veebikaamera-post-v2-standalone (Autodesk Fusion 360 design; units mm, degrees)
part number: 2026-10-23-17-59-02-011
part number: 2026-10-23-17-59-03-726
part number: 2026-10-23-17-59-05-380
part number: 2026-10-23-18-11-50-631
part number: 2026-10-23-18-11-50-740
Autodesk Fusion 360 part; units mm, degrees
ref_plane "WorkPlane1" through (0, 0, 7.28) normal (0, 0, 1) x (1, 0, 0) in component "webcam_post_lower"
sketch "Sketch1" plane through (0, 0, 7.28) normal (0, 0, 1) x (1, 0, 0) in component "webcam_post_lower"
  line L0 (-332.65, -126.4) -> (-408.35, -126.4)
  line L1 (-412.1, -130.15) -> (-412.1, -205.85)
  line L2 (-408.35, -209.6) -> (-332.65, -209.6)
  line L3 (-328.9, -205.85) -> (-328.9, -130.15)
  arc A0 (-408.35, -126.4) -> (-412.1, -130.15) centre (-408.35, -130.15) ccw
  arc A1 (-412.1, -205.85) -> (-408.35, -209.6) centre (-408.35, -205.85) ccw
  arc A2 (-332.65, -209.6) -> (-328.9, -205.85) centre (-332.65, -205.85) ccw
  arc A3 (-328.9, -130.15) -> (-332.65, -126.4) centre (-332.65, -130.15) ccw
  constraint tangent L0 A0
  constraint tangent L1 A0
  constraint tangent L1 A1
  constraint tangent L2 A1
  constraint tangent L2 A2
  constraint tangent L3 A2
  constraint tangent L3 A3
  constraint tangent L0 A3
extrude "Extrude1" add sketch "Sketch1" along normal blind 6 makes body 1 in component "webcam_post_lower"
ref_plane "WorkPlane2" through (0, 0, 7.28) normal (0, 0, 1) x (1, 0, 0) in component "webcam_post_lower"
sketch "Sketch2" plane through (0, 0, 7.28) normal (0, 0, 1) x (1, 0, 0) in component "webcam_post_lower"
  line L0 (-375.11, -171.11) -> (-407.89, -171.11)
  line L1 (-409.39, -172.61) -> (-409.39, -205.39)
  line L2 (-407.89, -206.89) -> (-375.11, -206.89)
  line L3 (-373.61, -205.39) -> (-373.61, -172.61)
  arc A0 (-407.89, -171.11) -> (-409.39, -172.61) centre (-407.89, -172.61) ccw
  arc A1 (-409.39, -205.39) -> (-407.89, -206.89) centre (-407.89, -205.39) ccw
  arc A2 (-375.11, -206.89) -> (-373.61, -205.39) centre (-375.11, -205.39) ccw
  arc A3 (-373.61, -172.61) -> (-375.11, -171.11) centre (-375.11, -172.61) ccw
  line L4 (-375.11, -129.11) -> (-407.89, -129.11)
  line L5 (-409.39, -130.61) -> (-409.39, -163.39)
  line L6 (-407.89, -164.89) -> (-375.11, -164.89)
  line L7 (-373.61, -163.39) -> (-373.61, -130.61)
  arc A4 (-407.89, -129.11) -> (-409.39, -130.61) centre (-407.89, -130.61) ccw
  arc A5 (-409.39, -163.39) -> (-407.89, -164.89) centre (-407.89, -163.39) ccw
  arc A6 (-375.11, -164.89) -> (-373.61, -163.39) centre (-375.11, -163.39) ccw
  arc A7 (-373.61, -130.61) -> (-375.11, -129.11) centre (-375.11, -130.61) ccw
  line L8 (-333.11, -171.11) -> (-365.89, -171.11)
  line L9 (-367.39, -172.61) -> (-367.39, -205.39)
  line L10 (-365.89, -206.89) -> (-333.11, -206.89)
  line L11 (-331.61, -205.39) -> (-331.61, -172.61)
  arc A8 (-365.89, -171.11) -> (-367.39, -172.61) centre (-365.89, -172.61) ccw
  arc A9 (-367.39, -205.39) -> (-365.89, -206.89) centre (-365.89, -205.39) ccw
  arc A10 (-333.11, -206.89) -> (-331.61, -205.39) centre (-333.11, -205.39) ccw
  arc A11 (-331.61, -172.61) -> (-333.11, -171.11) centre (-333.11, -172.61) ccw
  line L12 (-333.11, -129.11) -> (-365.89, -129.11)
  line L13 (-367.39, -130.61) -> (-367.39, -163.39)
  line L14 (-365.89, -164.89) -> (-333.11, -164.89)
  line L15 (-331.61, -163.39) -> (-331.61, -130.61)
  arc A12 (-365.89, -129.11) -> (-367.39, -130.61) centre (-365.89, -130.61) ccw
  arc A13 (-367.39, -163.39) -> (-365.89, -164.89) centre (-365.89, -163.39) ccw
  arc A14 (-333.11, -164.89) -> (-331.61, -163.39) centre (-333.11, -163.39) ccw
  arc A15 (-331.61, -130.61) -> (-333.11, -129.11) centre (-333.11, -130.61) ccw
  constraint tangent L0 A0
  constraint tangent L1 A0
  constraint tangent L1 A1
  constraint tangent L2 A1
  constraint tangent L2 A2
  constraint tangent L3 A2
  constraint tangent L3 A3
  constraint tangent L0 A3
  constraint tangent L4 A4
  constraint tangent L5 A4
  constraint tangent L5 A5
  constraint tangent L6 A5
  constraint tangent L6 A6
  constraint tangent L7 A6
  constraint tangent L7 A7
  constraint tangent L4 A7
  constraint tangent L8 A8
  constraint tangent L9 A8
  constraint tangent L9 A9
  constraint tangent L10 A9
  constraint tangent L10 A10
  constraint tangent L11 A10
  constraint tangent L11 A11
  constraint tangent L8 A11
  constraint tangent L12 A12
  constraint tangent L13 A12
  constraint tangent L13 A13
  constraint tangent L14 A13
  constraint tangent L14 A14
  constraint tangent L15 A14
  constraint tangent L15 A15
  constraint tangent L12 A15
extrude "Extrude2" add sketch "Sketch2" against normal blind 4.65 bodies 1 in component "webcam_post_lower"
chamfer "Chamfer1" distance 0.5 angle 45 32 edges at (-349.5, -129.11, 2.63) (-332.0493, -129.5493, 2.63) (-331.61, -147, 2.63) (-332.0493, -164.4507, 2.63) (-349.5, -164.89, 2.63) (-366.9507, -164.4507, 2.63) (-367.39, -147, 2.63) (-366.9507, -129.5493, 2.63) (-391.5, -171.11, 2.63) (-374.0493, -171.5493, 2.63) (-373.61, -189, 2.63) (-374.0493, -206.4507, 2.63) (-391.5, -206.89, 2.63) (-408.9507, -206.4507, 2.63) (-409.39, -189, 2.63) (-408.9507, -171.5493, 2.63) (-391.5, -129.11, 2.63) (-374.0493, -129.5493, 2.63) (-373.61, -147, 2.63) (-374.0493, -164.4507, 2.63) (-391.5, -164.89, 2.63) (-408.9507, -164.4507, 2.63) (-409.39, -147, 2.63) (-408.9507, -129.5493, 2.63) (-349.5, -171.11, 2.63) (-332.0493, -171.5493, 2.63) (-331.61, -189, 2.63) (-332.0493, -206.4507, 2.63) (-349.5, -206.89, 2.63) (-366.9507, -206.4507, 2.63) (-367.39, -189, 2.63) (-366.9507, -171.5493, 2.63) tangent chain off on bodies 1 in component "webcam_post_lower"
ref_plane "WorkPlane3" through (0, 0, 7.28) normal (0, 0, 1) x (1, 0, 0) in component "webcam_post_lower"
sketch "Sketch3" plane through (0, 0, 7.28) normal (0, 0, 1) x (1, 0, 0) in component "webcam_post_lower"
  line L0 (-382.1, -179.6) -> (-412.1, -179.6)
  line L1 (-412.1, -179.6) -> (-509.5955, -236.7941)
  line L2 (-509.5955, -236.7941) -> (-509.5955, -266.7941)
  line L3 (-509.5955, -266.7941) -> (-479.5955, -266.7941)
  line L4 (-479.5955, -266.7941) -> (-382.1, -209.6)
  line L5 (-382.1, -209.6) -> (-382.1, -179.6)
extrude "Extrude3" add sketch "Sketch3" along normal blind 30 bodies 1 in component "webcam_post_lower"
ref_plane "WorkPlane4" through (0, 0, 7.28) normal (0, 0, 1) x (1, 0, 0) in component "webcam_post_lower"
sketch "Sketch4" plane through (0, 0, 7.28) normal (0, 0, 1) x (1, 0, 0) in component "webcam_post_lower"
  line L0 (-385.1, -182.6) -> (-409.1, -182.6)
  line L1 (-409.1, -182.6) -> (-506.5955, -239.7941)
  line L2 (-506.5955, -239.7941) -> (-506.5955, -263.7941)
  line L3 (-506.5955, -263.7941) -> (-482.5955, -263.7941)
  line L4 (-482.5955, -263.7941) -> (-385.1, -206.6)
  line L5 (-385.1, -206.6) -> (-385.1, -182.6)
extrude "Extrude4" cut sketch "Sketch4" along normal blind 27 bodies 1 in component "webcam_post_lower"
ref_plane "WorkPlane5" through (0, 0, 7.28) normal (0, 0, 1) x (1, 0, 0) in component "webcam_post_lower"
sketch "Sketch5" plane through (0, 0, 7.28) normal (0, 0, 1) x (1, 0, 0) in component "webcam_post_lower"
  line L0 (-479.5955, -236.7941) -> (-509.5955, -236.7941)
  line L1 (-509.5955, -236.7941) -> (-509.5955, -266.7941)
  line L2 (-509.5955, -266.7941) -> (-479.5955, -266.7941)
  line L3 (-479.5955, -266.7941) -> (-479.5955, -236.7941)
  line L4 (-482.5955, -239.7941) -> (-506.5955, -239.7941)
  line L5 (-506.5955, -239.7941) -> (-506.5955, -263.7941)
  line L6 (-506.5955, -263.7941) -> (-482.5955, -263.7941)
  line L7 (-482.5955, -263.7941) -> (-482.5955, -239.7941)
extrude "Extrude5" add sketch "Sketch5" along normal blind 237.72 bodies 1 in component "webcam_post_lower"
ref_plane "WorkPlane6" through (0, -251.7941, 0) normal (0, 1, 0) x (0, 0, 1) in component "webcam_post_lower"
sketch "Sketch6" plane through (0, -251.7941, 0) normal (0, 1, 0) x (1, 0, 0) in component "webcam_post_lower"
  line L0 (-509.4955, -7.28) -> (-539.5955, -7.28)
  line L1 (-539.5955, -7.28) -> (-509.4955, -107.28)
  line L2 (-509.4955, -107.28) -> (-509.4955, -7.28)
extrude "Extrude6" add sketch "Sketch6" along normal mid plane 4 bodies 1 in component "webcam_post_lower"
ref_plane "WorkPlane7" through (-494.5955, 0, 0) normal (1, 0, 0) x (0, 1, 0) in component "webcam_post_lower"
sketch "Sketch7" plane through (-494.5955, 0, 0) normal (1, 0, 0) x (0, 0, -1) in component "webcam_post_lower"
  line L0 (-7.28, -266.6941) -> (-7.28, -296.7941)
  line L1 (-7.28, -296.7941) -> (-107.28, -266.6941)
  line L2 (-107.28, -266.6941) -> (-7.28, -266.6941)
extrude "Extrude7" add sketch "Sketch7" along normal mid plane 4 bodies 1 in component "webcam_post_lower"
ref_plane "WorkPlane8" through (-494.5955, 0, 0) normal (1, 0, 0) x (0, 1, 0) in component "webcam_post_lower"
sketch "Sketch8" plane through (-494.5955, 0, 0) normal (1, 0, 0) x (0, 0, -1) in component "webcam_post_lower"
  circle A0 centre (-227.5, -251.7941) radius 1.65
extrude "Extrude8" cut sketch "Sketch8" along normal mid plane 40 bodies 1 in component "webcam_post_lower"
ref_plane "WorkPlane1" through (0, 0, 210) normal (0, 0, 1) x (1, 0, 0) in component "webcam_post_upper"
sketch "Sketch1 (2)" plane through (0, 0, 210) normal (0, 0, 1) x (1, 0, 0) in component "webcam_post_upper"
  line L0 (-482.7955, -239.9941) -> (-506.3955, -239.9941)
  line L1 (-506.3955, -239.9941) -> (-506.3955, -263.5941)
  line L2 (-506.3955, -263.5941) -> (-482.7955, -263.5941)
  line L3 (-482.7955, -263.5941) -> (-482.7955, -239.9941)
  line L4 (-485.7955, -242.9941) -> (-503.3955, -242.9941)
  line L5 (-503.3955, -242.9941) -> (-503.3955, -260.5941)
  line L6 (-503.3955, -260.5941) -> (-485.7955, -260.5941)
  line L7 (-485.7955, -260.5941) -> (-485.7955, -242.9941)
extrude "Extrude1'" add sketch "Sketch1 (2)" along normal blind 38 separate body makes body 2 in component "webcam_post_upper"
ref_plane "WorkPlane2" through (0, 0, 245) normal (0, 0, 1) x (1, 0, 0) in component "webcam_post_upper"
sketch "Sketch2 (2)" plane through (0, 0, 245) normal (0, 0, 1) x (1, 0, 0) in component "webcam_post_upper"
  line L0 (-479.5955, -236.7941) -> (-509.5955, -236.7941)
  line L1 (-509.5955, -236.7941) -> (-509.5955, -266.7941)
  line L2 (-509.5955, -266.7941) -> (-479.5955, -266.7941)
  line L3 (-479.5955, -266.7941) -> (-479.5955, -236.7941)
  line L4 (-485.7955, -242.9941) -> (-503.3955, -242.9941)
  line L5 (-503.3955, -242.9941) -> (-503.3955, -260.5941)
  line L6 (-503.3955, -260.5941) -> (-485.7955, -260.5941)
  line L7 (-485.7955, -260.5941) -> (-485.7955, -242.9941)
extrude "Extrude2'" add sketch "Sketch2 (2)" along normal blind 3 bodies 2 in component "webcam_post_upper"
ref_plane "WorkPlane3" through (0, 0, 245) normal (0, 0, 1) x (1, 0, 0) in component "webcam_post_upper"
sketch "Sketch3 (2)" plane through (0, 0, 245) normal (0, 0, 1) x (1, 0, 0) in component "webcam_post_upper"
  line L0 (-479.5955, -236.7941) -> (-509.5955, -236.7941)
  line L1 (-509.5955, -236.7941) -> (-509.5955, -266.7941)
  line L2 (-509.5955, -266.7941) -> (-479.5955, -266.7941)
  line L3 (-479.5955, -266.7941) -> (-479.5955, -236.7941)
  line L4 (-482.5955, -239.7941) -> (-506.5955, -239.7941)
  line L5 (-506.5955, -239.7941) -> (-506.5955, -263.7941)
  line L6 (-506.5955, -263.7941) -> (-482.5955, -263.7941)
  line L7 (-482.5955, -263.7941) -> (-482.5955, -239.7941)
extrude "Extrude3'" add sketch "Sketch3 (2)" along normal blind 219 bodies 2 in component "webcam_post_upper"
ref_plane "WorkPlane4" through (0, 0, 464) normal (0, 0, 1) x (1, 0, 0) in component "webcam_post_upper"
sketch "Sketch4 (2)" plane through (0, 0, 464) normal (0, 0, 1) x (1, 0, 0) in component "webcam_post_upper"
  line L0 (-477.5955, -231.7941) -> (-511.5955, -231.7941)
  line L1 (-514.5955, -234.7941) -> (-514.5955, -268.7941)
  line L2 (-511.5955, -271.7941) -> (-477.5955, -271.7941)
  line L3 (-474.5955, -268.7941) -> (-474.5955, -234.7941)
  arc A0 (-511.5955, -231.7941) -> (-514.5955, -234.7941) centre (-511.5955, -234.7941) ccw
  arc A1 (-514.5955, -268.7941) -> (-511.5955, -271.7941) centre (-511.5955, -268.7941) ccw
  arc A2 (-477.5955, -271.7941) -> (-474.5955, -268.7941) centre (-477.5955, -268.7941) ccw
  arc A3 (-474.5955, -234.7941) -> (-477.5955, -231.7941) centre (-477.5955, -234.7941) ccw
  circle A4 centre (-494.5955, -251.7941) radius 3.3
  constraint tangent L0 A0
  constraint tangent L1 A0
  constraint tangent L1 A1
  constraint tangent L2 A1
  constraint tangent L2 A2
  constraint tangent L3 A2
  constraint tangent L3 A3
  constraint tangent L0 A3
extrude "Extrude4'" [suppressed] in component "webcam_post_upper"
ref_plane "WorkPlane5" through (-509.5955, 0, 0) normal (1, 0, 0) x (0, 1, 0) in component "webcam_post_upper"
sketch "Sketch5 (2)" plane through (-509.5955, 0, 0) normal (1, 0, 0) x (0, 0, -1) in component "webcam_post_upper"
  line L0 (-424, -258.7941) -> (-456, -258.7941)
  line L1 (-456, -258.7941) -> (-456, -244.7941)
  line L2 (-456, -244.7941) -> (-424, -244.7941)
  line L3 (-424, -244.7941) -> (-424, -258.7941)
extrude "Extrude5'" cut sketch "Sketch5 (2)" along normal mid plane 6 bodies 2 in component "webcam_post_upper"
ref_plane "WorkPlane6" through (-494.5955, 0, 0) normal (1, 0, 0) x (0, 1, 0) in component "webcam_post_upper"
sketch "Sketch6 (2)" plane through (-494.5955, 0, 0) normal (1, 0, 0) x (0, 0, -1) in component "webcam_post_upper"
  circle A0 centre (-227.5, -251.7941) radius 1.65
extrude "Extrude6'" cut sketch "Sketch6 (2)" along normal mid plane 40 bodies 2 in component "webcam_post_upper"
ref_plane "WorkPlane7" through (0, 0, 464) normal (0, 0, 1) x (1, 0, 0) in component "webcam_post_upper"
sketch "Sketch7 (2)" plane through (0, 0, 464) normal (0, 0, 1) x (1, 0, 0) in component "webcam_post_upper"
  line L0 (-499.4423, -288.3641) -> (-459.971, -254.0522)
  line L1 (-459.971, -254.0522) -> (-492.0129, -217.1922)
  line L2 (-492.0129, -217.1922) -> (-531.4842, -251.5041)
  line L3 (-531.4842, -251.5041) -> (-499.4423, -288.3641)
extrude "Extrude7'" add sketch "Sketch7 (2)" along normal blind 13 bodies 2 in component "webcam_post_upper"
ref_plane "WorkPlane8" through (0, 0, 470) normal (0, 0, 1) x (1, 0, 0) in component "webcam_post_upper"
sketch "Sketch8 (2)" plane through (0, 0, 470) normal (0, 0, 1) x (1, 0, 0) in component "webcam_post_upper"
  line L0 (-499.1463, -284.1318) -> (-461.1844, -251.1321)
  line L1 (-461.1844, -251.1321) -> (-489.29, -218.8003)
  line L2 (-489.29, -218.8003) -> (-527.2519, -251.8001)
  line L3 (-527.2519, -251.8001) -> (-499.1463, -284.1318)
extrude "Extrude8'" cut sketch "Sketch8 (2)" along normal blind 7 bodies 2 in component "webcam_post_upper"
ref_plane "WorkPlane9" through (0, 0, 470) normal (0, 0, 1) x (1, 0, 0) in component "webcam_post_upper"
sketch "Sketch9" plane through (0, 0, 470) normal (0, 0, 1) x (1, 0, 0) in component "webcam_post_upper"
  line L0 (-499.9776, -260.8452) -> (-484.8834, -247.724)
  line L1 (-484.8834, -247.724) -> (-489.2134, -242.743)
  line L2 (-489.2134, -242.743) -> (-504.3076, -255.8641)
  line L3 (-504.3076, -255.8641) -> (-499.9776, -260.8452)
extrude "Extrude9" cut sketch "Sketch9" against normal blind 7 bodies 2 in component "webcam_post_upper"
ref_plane "WorkPlane1" through (0, 0, -10.88) normal (0, 0, 1) x (1, 0, 0) in component "Verbatim_AWC-03_placeholder"
sketch "Sketch1 (3)" plane through (0, 0, -10.88) normal (0, 0, 1) x (1, 0, 0) in component "Verbatim_AWC-03_placeholder"
  line L0 (-46.5, -21.02) -> (-2, -21.02)
  line L1 (0, -19.02) -> (0, 19.02)
  line L2 (-2, 21.02) -> (-46.5, 21.02)
  line L3 (-48.5, 19.02) -> (-48.5, -19.02)
  arc A0 (-2, -21.02) -> (0, -19.02) centre (-2, -19.02) ccw
  arc A1 (0, 19.02) -> (-2, 21.02) centre (-2, 19.02) ccw
  arc A2 (-46.5, 21.02) -> (-48.5, 19.02) centre (-46.5, 19.02) ccw
  arc A3 (-48.5, -19.02) -> (-46.5, -21.02) centre (-46.5, -19.02) ccw
  constraint tangent L0 A0
  constraint tangent L1 A0
  constraint tangent L1 A1
  constraint tangent L2 A1
  constraint tangent L2 A2
  constraint tangent L3 A2
  constraint tangent L3 A3
  constraint tangent L0 A3
extrude "Extrude1''" add sketch "Sketch1 (3)" along normal blind 10.88 separate body makes body 3 in component "Verbatim_AWC-03_placeholder"
ref_plane "WorkPlane1" through (0, 0, 0) normal (0, 0, 1) x (1, 0, 0) in component "Verbatim_AWC-03_head"
sketch "Sketch1 (4)" plane through (0, 0, 0) normal (0, 0, 1) x (1, 0, 0) in component "Verbatim_AWC-03_head"
  line L0 (-4, -21.02) -> (4, -21.02)
  line L1 (6, -19.02) -> (6, 19.02)
  line L2 (4, 21.02) -> (-4, 21.02)
  line L3 (-6, 19.02) -> (-6, -19.02)
  arc A0 (4, -21.02) -> (6, -19.02) centre (4, -19.02) ccw
  arc A1 (6, 19.02) -> (4, 21.02) centre (4, 19.02) ccw
  arc A2 (-4, 21.02) -> (-6, 19.02) centre (-4, 19.02) ccw
  arc A3 (-6, -19.02) -> (-4, -21.02) centre (-4, -19.02) ccw
  constraint tangent L0 A0
  constraint tangent L1 A0
  constraint tangent L1 A1
  constraint tangent L2 A1
  constraint tangent L2 A2
  constraint tangent L3 A2
  constraint tangent L3 A3
  constraint tangent L0 A3
extrude "Extrude1'''" add sketch "Sketch1 (4)" along normal blind 12 separate body makes body 4 in component "Verbatim_AWC-03_head"
ref_plane "WorkPlane2" through (0, 0, 12) normal (0, 0, 1) x (1, 0, 0) in component "Verbatim_AWC-03_head"
sketch "Sketch2 (3)" plane through (0, 0, 12) normal (0, 0, 1) x (1, 0, 0) in component "Verbatim_AWC-03_head"
  line L0 (-7, -53) -> (7, -53)
  line L1 (15, -45) -> (15, 45)
  line L2 (7, 53) -> (-7, 53)
  line L3 (-15, 45) -> (-15, -45)
  arc A0 (7, -53) -> (15, -45) centre (7, -45) ccw
  arc A1 (15, 45) -> (7, 53) centre (7, 45) ccw
  arc A2 (-7, 53) -> (-15, 45) centre (-7, 45) ccw
  arc A3 (-15, -45) -> (-7, -53) centre (-7, -45) ccw
  constraint tangent L0 A0
  constraint tangent L1 A0
  constraint tangent L1 A1
  constraint tangent L2 A1
  constraint tangent L2 A2
  constraint tangent L3 A2
  constraint tangent L3 A3
  constraint tangent L0 A3
extrude "Extrude2''" add sketch "Sketch2 (3)" along normal blind 32 bodies 4 in component "Verbatim_AWC-03_head"
ref_plane "WorkPlane3" through (15, 0, 0) normal (1, 0, 0) x (0, 1, 0) in component "Verbatim_AWC-03_head"
sketch "Sketch3 (3)" plane through (15, 0, 0) normal (1, 0, 0) x (0, 0, -1) in component "Verbatim_AWC-03_head"
  circle A0 centre (-28, 0) radius 8
extrude "Extrude3''" add sketch "Sketch3 (3)" along normal blind 4 bodies 4 in component "Verbatim_AWC-03_head"
component "webcam_post_lower" placed x (1, 0, 0) y (0, 1, 0) z (0, 0, 1) at (0, 0, 0)
component "webcam_post_upper" placed x (1, 0, 0) y (0, 1, 0) z (0, 0, 1) at (0, 0, 0)
component "Verbatim_AWC-03_placeholder" placed x (0.75471, 0.656059, 0) y (-0.656059, 0.75471, 0) z (0, 0, 1) at (-476.2938, -235.8847, 480.88)
component "Verbatim_AWC-03_head" placed x (0.560859, 0.487547, -0.669131) y (-0.656059, 0.75471, 0) z (0.504999, 0.438989, 0.743145) at (-476.2938, -235.8847, 480.88)
equation "grid_top_z = 7.28 mm" comment "MG 400 rakis: grid top above robot floor"
equation "grid_clearance = 0.3 mm" comment "Gridfinity bin undersize per cell"
equation "foot_size = 35.78 mm" comment "Foot = narrowest socket 36.28 mm - 2 x 0.25 mm (as glass-input-holder-v2)"
equation "foot_corner_radius = 1.5 mm" comment "Larger than socket throat radius 1.14 mm"
equation "foot_depth = 4.65 mm" comment "Measured socket depth"
equation "foot_bottom_chamfer = 0.5 mm" comment "Lead-in chamfer on foot bottom"
equation "base_thickness = 6 mm" comment "2x2 base plate thickness (cells G-5, G-4, F-5, F-4)"
equation "post_r_from_J1 = 555 mm" comment "Post centre distance from J1 axis; arm+J4 housing+tool envelope is <= 515 mm"
equation "post_outer = 30 mm" comment "Square post outer size"
equation "post_wall = 3 mm" comment "Post wall; hollow so the USB cable runs inside"
equation "beam_height = 30 mm" comment "Cantilever beam from base to post, kept low (rule: > 60 mm not in the arm path)"
equation "split_z = 245 mm" comment "Split height: lower 242 mm, upper 260 mm, both fit the 270 mm printer Z"
equation "plate_top_z = 470 mm" comment "Camera plate top; camera body above ~495 mm, arm never rises above ~490 mm"
equation "plate_size = 40 mm" comment "Camera plate"
equation "plate_thickness = 6 mm" comment "Camera plate thickness"
equation "tripod_hole = 6.6 mm" comment "1/4in tripod screw clearance (Verbatim AWC-03 clip)"
equation "spigot_length = 35 mm" comment "Joint spigot length"
equation "spigot_clearance = 0.2 mm" comment "Joint clearance per side"
equation "pin_hole = 3.3 mm" comment "M3 cross pin through the joint, removes joint play"
equation "gusset_height = 100 mm" comment "Ribs on the outer side of the post (outside the arm envelope)"
equation "gusset_length = 30 mm" comment "Rib length from the post face"
equation "gusset_thickness = 4 mm" comment "Rib thickness"
equation "d31 = foot_bottom_chamfer"
equation "clip_width = 42.04 mm" comment "MEASURED 23.10.26 (caliper): Verbatim AWC-03 lower clip leg width"
equation "clip_length = 48.5 mm" comment "MEASURED 23.10.26: lower clip leg length"
equation "clip_height = 10.88 mm" comment "MEASURED 23.10.26: lower clip leg thickness"
equation "clip_clearance = 0.4 mm" comment "Gap per side: clip slides in by hand, Lab 1 range 0.2-0.4 mm"
equation "cradle_depth = 7 mm" comment "Pocket depth; the 10.88 mm clip sticks out ~3.9 mm to grip it"
equation "cradle_wall = 3 mm" comment "Cradle wall thickness (3 sides, the hinge side is open)"
equation "cradle_yaw = 41 deg" comment "Open side faces the table (same as computed camera yaw)"
equation "screw_slot_length = 20 mm" comment "1/4in screw slot along the clip: thread position on the clip not measured yet"
named bodies: "webcam_post_lower", "webcam_post_upper", "clip_lower_leg_48.5x42.04x10.88", "camera_head_lens"
